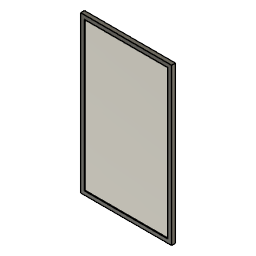
Gondola - Ends (Autodesk Fusion 360 design; units mm, degrees)
Autodesk Fusion 360 part; units mm, degrees
sketch "Sketch1" plane through (0, 0, 0) normal (0, 1, 0) x (1, 0, 0)
  line L0 (0, 0) -> (700, 0)
  line L1 (700, 0) -> (700, -1200)
  line L2 (700, -1200) -> (0, -1200)
  line L3 (0, -1200) -> (0, 0)
  dimension "d1" = 700
  dimension "d2" = 1200
  constraint horizontal L0
  constraint vertical L1
  constraint horizontal L2
  constraint vertical L3
  constraint coincident L0.start L3.end
  measures "d1" distance of L0.start L0.end
  measures "d2" distance of L0.start L2.end
extrude "Extrude1" add sketch "Sketch1" along normal blind 20
sketch "Sketch2" plane through (0, 0, 0) normal (0, -1, 0) x (1, 0, 0)
  line L0 (700, 1200) -> (0, 1200)
  line L1 (0, 1200) -> (0, 0)
  line L2 (0, 0) -> (700, 0)
  line L3 (700, 0) -> (700, 1200)
  line L4 (0, 1200) -> (700, 1200)
  line L5 (700, 1200) -> (700, 0)
  line L6 (700, 0) -> (0, 0)
  line L7 (0, 0) -> (0, 1200)
  line L8 (0, 1200) -> (30, 1200)
  line L9 (30, 1200) -> (30, 1170)
  line L10 (30, 1170) -> (0, 1170)
  line L11 (0, 1170) -> (0, 1200)
  line L12 (30, 1170) -> (670, 1170)
  line L13 (670, 1170) -> (670, 30)
  line L14 (670, 30) -> (30, 30)
  line L15 (30, 30) -> (30, 1170)
  dimension "d5" = 30
  dimension "d6" = 30
  dimension "d7" = 640
  dimension "d8" = 1140
  constraint horizontal L4
  constraint vertical L5
  constraint horizontal L6
  constraint vertical L7
  constraint coincident L2.end L3.start
  constraint coincident L0.end L1.start
  constraint horizontal L8
  constraint vertical L9
  constraint horizontal L10
  constraint vertical L11
  constraint horizontal L12
  constraint vertical L13
  constraint horizontal L14
  constraint vertical L15
  measures "d5" distance of L0.end L8.end
  measures "d6" distance of L0.end L10.end
  measures "d7" distance of L9.end L12.end
  measures "d8" distance of L9.end L14.end
extrude "Extrude2" add sketch "Sketch2" along normal blind 5
sketch "Sketch3" plane through (0, 20, 0) normal (0, 1, 0) x (-1, 0, 0)
  line L0 (0, 1200) -> (-700, 1200)
  line L1 (-700, 1200) -> (-700, 0)
  line L2 (-700, 0) -> (0, 0)
  line L3 (0, 0) -> (0, 1200)
  line L4 (-700, 0) -> (-670, 0)
  line L5 (-670, 0) -> (-670, 30)
  line L6 (-670, 30) -> (-700, 30)
  line L7 (-700, 30) -> (-700, 0)
  line L8 (-670, 30) -> (-30, 30)
  line L9 (-30, 30) -> (-30, 1170)
  line L10 (-30, 1170) -> (-670, 1170)
  line L11 (-670, 1170) -> (-670, 30)
  dimension "d11" = 30
  dimension "d12" = 30
  dimension "d13" = 640
  dimension "d14" = 1140
  constraint horizontal L4
  constraint vertical L5
  constraint horizontal L6
  constraint vertical L7
  constraint coincident L1.end L2.start
  constraint horizontal L8
  constraint vertical L9
  constraint horizontal L10
  constraint vertical L11
  measures "d11" distance of L1.end L4.end
  measures "d12" distance of L1.end L6.end
  measures "d13" distance of L5.end L8.end
  measures "d14" distance of L5.end L10.end
extrude "Extrude3" add sketch "Sketch3" along normal blind 5
